Thigh_right_goupille_genoux_v2 (Autodesk Fusion 360 design; units mm, degrees)
Autodesk Fusion 360 part; units mm, degrees
sketch "sketch 645" plane through (0, -31.5, 0) normal (0, -1, 0) x (1, 0, 0)
  circle A0 centre (0, -415) radius 4
extrude "Extrude1" add sketch "sketch 645" along normal blind 11
sketch "sketch 658" plane through (0, -31.5, 0) normal (0, -1, 0) x (1, 0, 0)
  circle A0 centre (0, -415) radius 3
  circle A1 centre (0, -415) radius 4
extrude "Extrude2" cut sketch "sketch 658" along normal blind 10
sketch "sketch 673" plane through (0, -31.5, 0) normal (0, -1, 0) x (1, 0, 0)
  circle A0 centre (0, -415) radius 3
  circle A1 centre (0, -415) radius 4
extrude "Extrude3" add sketch "sketch 673" along normal blind 9
sketch "sketch 688" plane through (0, -31.5, 0) normal (0, -1, 0) x (1, 0, 0)
  circle A0 centre (0, -415) radius 4
extrude "Extrude4" add sketch "sketch 688" against normal blind 44
sketch "sketch 700" plane through (0, -31.5, 0) normal (0, -1, 0) x (1, 0, 0)
  circle A0 centre (0, -415) radius 3
  circle A1 centre (0, -415) radius 4
extrude "Extrude5" cut sketch "sketch 700" against normal blind 43
sketch "sketch 715" plane through (0, -31.5, 0) normal (0, -1, 0) x (1, 0, 0)
  circle A0 centre (0, -415) radius 3
  circle A1 centre (0, -415) radius 4
extrude "Extrude6" add sketch "sketch 715" against normal blind 42
chamfer "Chamfer1" distance 1 angle 45 2 edges at (-3.7293, 10.5, -413.5535) (-3.7293, -40.5, -416.4465) tangent chain off
chamfer "Chamfer2" distance 0.4 angle 45 2 edges at (-3.7293, 12.5, -413.5535) (-3.7293, -42.5, -416.4465) tangent chain off
